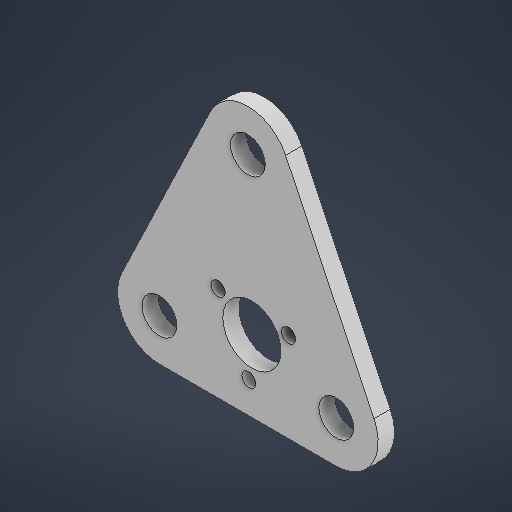
# Autodesk Inventor part: 1. support plate
Saved by Autodesk Inventor 2026.1 (Build 301233020, 233B)
## iProperties
Created: 2026-01-20
Part Number: 1. support plate
Material: Generic
Document SubType Name: Modeling
Designer: anith
Density: 1 g/cm^3
Appearance: Default
Author: anith
Autodesk Inventor part; units mm, degrees
ref_plane "YZ Plane" through (0, 0, 0) normal (1, 0, 0) x (0, 1, 0)
ref_plane "XZ Plane" through (0, 0, 0) normal (0, 1, 0) x (-1, 0, 0)
ref_plane "XY Plane" through (0, 0, 0) normal (0, 0, 1) x (1, 0, 0)
sketch "Sketch1" plane through (0, 0, 0) normal (0, 1, 0) x (-1, 0, 0)
  arc A0 (0, -18) -> (16.221, 7.8025) centre (0, 0) ccw
  circle A1 centre (0, 0) radius 7.5
  arc A2 (-92.221, 7.8025) -> (-76, -18) centre (-76, 0) ccw
  circle A3 centre (-76, 0) radius 7.5
  line L0 (0, -18) -> (-76, -18)
  arc A4 (-21.779, 86.8025) -> (-54.221, 86.8025) centre (-38, 79) ccw
  line L1 (-54.221, 86.8025) -> (-92.221, 7.8025)
  line L2 (-21.779, 86.8025) -> (16.221, 7.8025)
  circle A5 centre (-38, 79) radius 7.5
  circle A6 centre (-39.7284, 12.8895) radius 12.5
  circle A7 centre (-39.7284, 12.8895) radius 17.5 construction
  circle A8 centre (-38.4178, -4.5614) radius 3
  circle A9 centre (-39.7284, 12.8895) radius 17.5 construction
  circle A10 centre (-25.2709, 22.75) radius 3
  circle A11 centre (-39.7284, 12.8895) radius 17.5 construction
  circle A12 centre (-55.4967, 20.4798) radius 3
  point P0 (-38, -18)
  point P1 (-38, 97)
  dimension "d0" = 36
  dimension "d1" = 15
  dimension "d2" = 36
  dimension "d3" = 15
  dimension "d4" = 76
  dimension "d5" = 36
  dimension "d8" = 15
  dimension "d9" = 25
  dimension "d13" = 6
  dimension "d16" = 360
  dimension "d18" = 40.75
  dimension "d19" = 17.5
  dimension "d20" = 38
  dimension "d25" = 30.9118
  dimension "d26" = 48.2147
  dimension "d29" = 115
  constraints: 10 centre point, 7 coincident, 7 point on circle, 6 end point, 6 tangent, 1 horizontal, 1 midpoint, 20 other
  measures "d0" diameter of A0
  measures "d1" diameter of A1
  measures "d2" diameter of A2
  measures "d3" diameter of A3
  measures "d4" distance of A2.centre point (0, 0)
  measures "d5" diameter of A4
  measures "d8" diameter of A5
  measures "d9" diameter of A6
  measures "d13" diameter of A8
  measures "d18" distance from line of L0 A10.centre
  measures "d19" distance of A8.centre A6.centre
  measures "d20" horizontal distance of point (0, 0) A4.centre
  measures "d25" distance from line of A10.centre L2
  measures "d26" distance from line of point (-39.728, 12.889) L2
  measures "d29" distance from line of L0 point (-38, 97)
extrude "Extrusion1" add sketch "Sketch1" along normal blind 7
body "Solid1"
